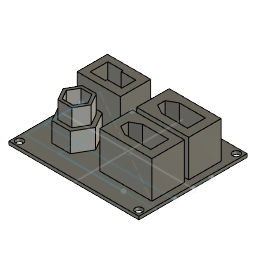
Direct source connector mount (Autodesk Fusion 360 design; units mm, degrees)
Autodesk Fusion 360 part; units mm, degrees
sketch "Sketch1" plane through (0, 0, 0) normal (0, 0, 1) x (1, 0, 0)
  line L0 (0, 0) -> (60, 0)
  line L1 (60, 0) -> (60, 50)
  line L2 (60, 50) -> (0, 50)
  line L3 (0, 50) -> (0, 0)
  dimension "d1" = 60
  dimension "d2" = 50
  constraint horizontal L0
  constraint vertical L1
  constraint horizontal L2
  constraint vertical L3
  constraint coincident L0.start L3.end
  measures "d1" distance of L0.start L0.end
  measures "d2" distance of L0.start L2.end
extrude "Extrude1" add sketch "Sketch1" along normal blind 1.5
sketch "Sketch2" plane through (0, 0, 0) normal (0, 0, -1) x (1, 0, 0)
  line L0 (0, 0) -> (0, -50)
  line L1 (0, -50) -> (60, -50)
  line L2 (60, -50) -> (60, 0)
  line L3 (60, 0) -> (0, 0)
  line L4 (30, -50) -> (30, 0)
  line L5 (60, -25) -> (0, -25)
  line L6 (60, -8) -> (0, -8)
  line L7 (0, -8) -> (0, -42)
  line L8 (60, -8) -> (0, -42) construction
  point P0 (30, -25)
  dimension "d6" = 34
  constraint midpoint L1 L4.start
  constraint midpoint L3 L4.end
  constraint midpoint L2 L5.start
  constraint midpoint L0 L5.end
  constraint horizontal L6
  constraint perpendicular L6 L7
  constraint coincident L8 P0
  constraint midpoint L4 P0
  measures "d6" distance of L6.end L7.end
sketch "Sketch3" plane through (0, 0, 0) normal (0, 0, -1) x (1, 0, 0)
  line L0 (60, -25) -> (60, -33.5)
  line L1 (0, -33.5) -> (0, -16.5)
  line L2 (0, -16.5) -> (60, -16.5)
  dimension "d7" = 8.5
  dimension "d8" = 17
  constraint vertical L0
  measures "d7" distance of L0.start L0.end
  measures "d8" distance of L0.end L2.end
sketch "Sketch4" plane through (0, 0, 0) normal (0, 0, -1) x (1, 0, 0)
  line L0 (45, -8) -> (15, -8)
  line L1 (15, -8) -> (15, -42)
  constraint perpendicular L0 L1
sketch "Sketch5" plane through (0, 0, 0) normal (0, 0, -1) x (1, 0, 0)
  line L0 (36.9, -29.4) -> (53.1, -29.4)
  line L1 (53.1, -29.4) -> (53.1, -37.6)
  line L2 (53.1, -37.6) -> (36.9, -37.6)
  line L3 (36.9, -37.6) -> (36.9, -29.4)
  line L4 (36.9, -29.4) -> (53.1, -37.6) construction
  line L5 (53.1, -29.4) -> (36.9, -37.6) construction
  line L6 (36.9, -33.5) -> (36.9, -32)
  line L7 (36.9, -33.5) -> (36.9, -31.75)
  line L8 (36.9, -31.75) -> (36.9, -35.25)
  line L9 (53.1, -37.6) -> (41.1, -37.6)
  line L10 (53.1, -29.4) -> (41.1, -29.4)
  line L11 (36.9, -31.75) -> (41.1, -29.4)
  line L12 (36.9, -35.25) -> (41.1, -37.6)
  line L13 (36.9, -12.4) -> (53.1, -12.4)
  line L14 (36.9, -16.5) -> (36.9, -15)
  line L15 (36.9, -18.25) -> (41.1, -20.6)
  line L16 (36.9, -14.75) -> (36.9, -18.25)
  line L17 (36.9, -20.6) -> (36.9, -12.4)
  line L18 (53.1, -12.4) -> (41.1, -12.4)
  line L19 (36.9, -12.4) -> (53.1, -20.6) construction
  line L20 (53.1, -20.6) -> (36.9, -20.6)
  line L21 (53.1, -20.6) -> (41.1, -20.6)
  line L22 (53.1, -12.4) -> (53.1, -20.6)
  line L23 (53.1, -12.4) -> (36.9, -20.6) construction
  line L24 (36.9, -14.75) -> (41.1, -12.4)
  line L25 (36.9, -16.5) -> (36.9, -14.75)
  line L26 (8.125, -29.46) -> (21.875, -29.46)
  line L27 (21.875, -29.46) -> (21.875, -37.54)
  line L28 (21.875, -37.54) -> (8.125, -37.54)
  line L29 (8.125, -37.54) -> (8.125, -29.46)
  line L30 (8.125, -29.46) -> (21.875, -37.54) construction
  line L31 (21.875, -29.46) -> (8.125, -37.54) construction
  line L32 (8.125, -37.54) -> (15.125, -37.54)
  line L33 (15.125, -37.54) -> (15.125, -29.46)
  line L34 (15.125, -29.46) -> (8.125, -29.46)
  line L35 (8.125, -29.46) -> (8.125, -37.54)
  line L36 (21.875, -33.5) -> (15, -33.5)
  line L37 (21.875, -36.7) -> (15, -36.7)
  line L38 (15, -36.7) -> (15, -30.3)
  line L39 (15, -30.3) -> (21.875, -30.3)
  line L40 (21.875, -30.3) -> (21.875, -36.7)
  line L41 (21.875, -36.7) -> (15, -30.3) construction
  line L42 (15, -36.7) -> (21.875, -30.3) construction
  point P0 (45, -33.5)
  point P1 (45, -16.5)
  point P2 (15, -33.5)
  point P3 (18.4375, -33.5)
  dimension "d9" = 16.2
  dimension "d10" = 8.2
  dimension "d11" = 1.75
  dimension "d12" = 3.5
  dimension "d13" = 12
  dimension "d14" = 12
  dimension "d15" = 16.2
  dimension "d16" = 8.2
  dimension "d17" = 1.75
  dimension "d18" = 3.5
  dimension "d19" = 12
  dimension "d20" = 12
  dimension "d21" = 13.75
  dimension "d22" = 8.08
  dimension "d23" = 7
  dimension "d24" = 8.08
  dimension "d25" = 6.875
  dimension "d26" = 6.4
  constraint horizontal L0
  constraint perpendicular L0 L1
  constraint parallel L0 L2
  constraint parallel L1 L3
  constraint coincident L4 P0
  constraint coincident L5 P0
  constraint midpoint L3 L6.start
  constraint coincident L3 L6.end
  constraint coincident L3 L7.end
  constraint parallel L3 L8
  constraint coincident L2 L9.end
  constraint coincident L0 L10.end
  constraint horizontal L13
  constraint perpendicular L13 L22
  constraint parallel L13 L20
  constraint parallel L17 L22
  constraint coincident P1 L19
  constraint coincident P1 L23
  constraint midpoint L14.start L17
  constraint coincident L14.end L17
  constraint coincident L16.start L17
  constraint parallel L16 L17
  constraint coincident L15.end L20
  constraint coincident L18.end L13
  constraint horizontal L26
  constraint perpendicular L26 L27
  constraint parallel L26 L28
  constraint parallel L27 L29
  constraint coincident L30 P2
  constraint coincident L31 P2
  constraint horizontal L32
  constraint vertical L33
  constraint horizontal L34
  constraint vertical L35
  constraint midpoint L27 L36.start
  constraint coincident P2 L36.end
  constraint horizontal L37
  constraint perpendicular L37 L38
  constraint parallel L37 L39
  constraint parallel L38 L40
  constraint coincident L41 P3
  constraint coincident L42 P3
  constraint midpoint L36 P3
  measures "d9" distance of L1.end L2.end
  measures "d10" distance of L0.end L1.end
  measures "d11" distance of L6.start L7.end
  measures "d12" distance of L7.end L8.end
  measures "d13" distance of L1.end L9.end
  measures "d14" distance of L0.end L10.end
  measures "d15" distance of L19.end L17.start
  measures "d16" distance of L19.end L13.end
  measures "d17" distance of L14.start L16.start
  measures "d18" distance of L15.start L16.start
  measures "d19" distance of L19.end L15.end
  measures "d20" distance of L13.end L18.end
  measures "d21" distance of L27.end L28.end
  measures "d22" distance of L26.end L27.end
  measures "d23" distance of L28.end L32.end
  measures "d24" distance of L28.end L26.start
  measures "d25" distance of L38.end L39.end
  measures "d26" distance of L37.end L38.end
sketch "Sketch6" plane through (0, 0, 0) normal (0, 0, -1) x (1, 0, 0)
  circle A0 centre (15, -16.5) radius 5
  line L0 (20, -16.5) -> (17.5, -12.1699)
  line L1 (17.5, -12.1699) -> (12.5, -12.1699)
  line L2 (12.5, -12.1699) -> (10, -16.5)
  line L3 (10, -16.5) -> (12.5, -20.8301)
  line L4 (12.5, -20.8301) -> (17.5, -20.8301)
  line L5 (17.5, -20.8301) -> (20, -16.5)
  point P0 (15, -16.5)
  dimension "d27" = 10
  dimension "d28" = 5
  constraint coincident A0 L4.end
  constraint coincident A0 L0.start
  measures "d27" diameter of A0
  measures "d28" distance of L0.start L4.end
sketch "Sketch7" plane through (0, 0, 1.5) normal (0, 0, 1) x (-1, 0, 0)
  line L0 (0, -50) -> (0, 0)
  line L1 (0, 0) -> (-60, 0)
  line L2 (-60, 0) -> (-60, -50)
  line L3 (-60, -50) -> (0, -50)
  line L4 (-22.5, -38) -> (-7.5, -38)
  line L5 (-7.5, -38) -> (-7.5, -29)
  line L6 (-7.5, -29) -> (-22.5, -29)
  line L7 (-22.5, -29) -> (-22.5, -38)
  line L8 (-22.5, -38) -> (-7.5, -29) construction
  line L9 (-7.5, -38) -> (-22.5, -29) construction
  line L10 (-55, -11) -> (-35, -11)
  line L11 (-35, -11) -> (-35, -22)
  line L12 (-35, -22) -> (-55, -22)
  line L13 (-55, -22) -> (-55, -11)
  line L14 (-55, -28) -> (-35, -28)
  line L15 (-35, -28) -> (-35, -39)
  line L16 (-35, -39) -> (-55, -39)
  line L17 (-55, -39) -> (-55, -28)
  line L18 (-18.2501, -22.1291) -> (-11.7501, -22.1292)
  line L19 (-11.7501, -22.1292) -> (-8.5, -16.5001)
  line L20 (-8.5, -16.5001) -> (-11.7499, -10.8709)
  line L21 (-11.7499, -10.8709) -> (-18.2499, -10.8708)
  line L22 (-18.2499, -10.8708) -> (-21.5, -16.4999)
  line L23 (-21.5, -16.4999) -> (-18.2501, -22.1291)
  point P0 (-15, -33.5)
  point P1 (-15, -16.5)
  dimension "d29" = 6.5
  constraint horizontal L4
  constraint perpendicular L4 L5
  constraint parallel L4 L6
  constraint parallel L5 L7
  constraint coincident L8 P0
  constraint coincident L9 P0
  constraint horizontal L10
  constraint vertical L11
  constraint horizontal L12
  constraint vertical L13
  constraint horizontal L14
  constraint vertical L15
  constraint horizontal L16
  constraint vertical L17
  measures "d29" distance of L18.start P1
extrude "Extrude2" add sketch "Sketch7" along normal blind 17 contours L4 L5 L6 L7 | L10 L11 L12 L13 | L14 L15 L16 L17 | L18 L19 L20 L21 L22 L23
extrude "Extrude3" cut sketch "Sketch5" sketch "Sketch6" against normal blind 234872335 contours L0 L1 L2 L3 L6 L7 L8 L9 L10 L11 L12 | L13 L14 L15 L16 L17 L18 L20 L21 L22 L24 L25 | L26 L28 L29 L32 L33 L34 L35 L37 L38 L39 | L27 L33 L36 L39 L40 | L27 L33 L36 L37 L40 of sketch 2 contours L0 L1 L2 L3 L4 L5
extrude "Extrude4" cut 1 faces at (15.125, 34.5667, 12.3333) along direction (-1, 0, 0) blind 1
sketch "Sketch8" plane through (0, 0, 0) normal (0, 0, -1) x (1, 0, 0)
  line L0 (53.6, -38.1) -> (53.6, -28.9)
  line L1 (53.6, -28.9) -> (41.1, -28.9)
  line L2 (36.9, -31.75) -> (36.4, -31.75)
  line L3 (41.1, -28.9) -> (36.4639, -31.491)
  line L4 (41.1, -28.9) -> (46.411, -28.9) construction
  line L5 (53.6, -38.1) -> (41.1, -38.1)
  line L6 (41.1, -38.1) -> (36.4639, -35.509)
  line L7 (36.4639, -35.509) -> (36.4639, -31.491)
  line L8 (36.4639, -18.509) -> (36.4639, -14.491)
  line L9 (41.1, -11.9) -> (46.411, -11.9) construction
  line L10 (53.6, -21.1) -> (53.6, -11.9)
  line L11 (53.6, -21.1) -> (41.1, -21.1)
  line L12 (53.6, -11.9) -> (41.1, -11.9)
  line L13 (41.1, -11.9) -> (36.4639, -14.491)
  line L14 (36.9, -14.75) -> (36.4, -14.75)
  line L15 (41.1, -21.1) -> (36.4639, -18.509)
  line L16 (23, -39) -> (7, -39)
  line L17 (7, -39) -> (7, -28)
  line L18 (7, -28) -> (23, -28)
  line L19 (23, -28) -> (23, -39)
  circle A0 centre (15, -16.5) radius 6
  dimension "d36" = 9.2
  dimension "d37" = 0.5
  dimension "d38" = 150.8
  dimension "d39" = 5.311
  dimension "d40" = 150.8
  dimension "d41" = 9.2
  dimension "d42" = 0.5
  dimension "d43" = 150.8
  dimension "d44" = 5.311
  dimension "d45" = 150.8
  dimension "d46" = 12
  constraint perpendicular L0 L1
  constraint perpendicular L0 L2
  constraint horizontal L4
  constraint perpendicular L0 L5
  constraint perpendicular L2 L7
  constraint perpendicular L10 L12
  constraint perpendicular L10 L14
  constraint horizontal L9
  constraint perpendicular L10 L11
  constraint perpendicular L8 L14
  constraint horizontal L16
  constraint vertical L17
  constraint horizontal L18
  constraint vertical L19
  measures "d36" distance of L0.start L0.end
  measures "d37" distance of L2.start L2.end
  measures "d38" angle of L3 L4
  measures "d39" distance of L1.end L3.end
  measures "d40" angle of L5 L6
  measures "d41" distance of L10.start L10.end
  measures "d42" distance of L14.start L14.end
  measures "d43" angle of L9 L13
  measures "d44" distance of L8.end L9.start
  measures "d45" angle of L11 L15
  measures "d46" diameter of A0
sketch "Sketch9" plane through (0, 0, 0) normal (0, 0, -1) x (1, 0, 0)
  line L0 (57.5, -2.5) -> (2.5, -2.5)
  line L1 (2.5, -2.5) -> (2.5, -47.5)
  line L2 (2.5, -47.5) -> (57.5, -47.5)
  line L3 (57.5, -47.5) -> (57.5, -2.5)
  line L4 (57.5, -2.5) -> (2.5, -47.5) construction
  line L5 (2.5, -2.5) -> (57.5, -47.5) construction
  circle A0 centre (57.5, -47.5) radius 1.7
  circle A1 centre (2.5, -47.5) radius 1.7
  circle A2 centre (57.5, -2.5) radius 1.7
  circle A3 centre (2.5, -2.5) radius 1.7
  point P0 (30, -25)
  dimension "d47" = 55
  dimension "d48" = 45
  dimension "d49" = 3.4
  dimension "d50" = 3.4
  dimension "d51" = 3.4
  dimension "d52" = 3.4
  constraint horizontal L0
  constraint perpendicular L0 L1
  constraint parallel L0 L2
  constraint parallel L1 L3
  constraint coincident L4 P0
  constraint coincident L5 P0
  constraint coincident L2.end L3.start
  constraint coincident L1.end L2.start
  constraint coincident L0.start L3.end
  constraint coincident L0.end L1.start
  measures "d47" distance of L1.end L2.end
  measures "d48" distance of L0.end L1.end
  measures "d49" diameter of A0
  measures "d50" diameter of A1
  measures "d51" diameter of A2
  measures "d52" diameter of A3
extrude "Extrude5" cut sketch "Sketch9" against normal blind 6767 contours L0 L1 A3 | L0 L1 A3 | L0 L3 A2 | L0 L3 A2 | L1 L2 A1 | L1 L2 A1 | L2 L3 A0 | L2 L3 A0
sketch "Sketch10" plane through (0, 0, 1.5) normal (0, 0, 1) x (-1, 0, 0)
  line L0 (0, -50) -> (0, 0)
  line L1 (0, 0) -> (-60, 0)
  line L2 (-60, 0) -> (-60, -50)
  line L3 (-60, -50) -> (0, -50)
  line L4 (-21.5, -16.4999) -> (-18.2499, -10.8708)
  line L5 (-18.2499, -10.8708) -> (-11.7499, -10.8709)
  line L6 (-11.7499, -10.8709) -> (-8.5, -16.5001)
  line L7 (-8.5, -16.5001) -> (-11.7501, -22.1292)
  line L8 (-11.7501, -22.1292) -> (-18.2501, -22.1291)
  line L9 (-18.2501, -22.1291) -> (-21.5, -16.4999)
  line L10 (-55, -39) -> (-55, -28)
  line L11 (-55, -28) -> (-35, -28)
  line L12 (-35, -28) -> (-35, -39)
  line L13 (-35, -39) -> (-55, -39)
  line L14 (-22.5, -29) -> (-7.5, -29)
  line L15 (-7.5, -29) -> (-7.5, -38)
  line L16 (-7.5, -38) -> (-22.5, -38)
  line L17 (-22.5, -38) -> (-22.5, -29)
  line L18 (-55, -22) -> (-55, -11)
  line L19 (-55, -11) -> (-35, -11)
  line L20 (-35, -11) -> (-35, -22)
  line L21 (-35, -22) -> (-55, -22)
  circle A0 centre (-57.5, -2.5) radius 1.7
  circle A1 centre (-57.5, -47.5) radius 1.7
  circle A2 centre (-2.5, -2.5) radius 1.7
  circle A3 centre (-2.5, -47.5) radius 1.7
  line L22 (-23.5, -16.4999) -> (-19.2501, -23.8612)
  line L23 (-19.2501, -23.8612) -> (-10.7501, -23.8613)
  line L24 (-10.7501, -23.8613) -> (-6.5, -16.5001)
  line L25 (-6.5, -16.5001) -> (-10.7499, -9.1388)
  line L26 (-10.7499, -9.1388) -> (-19.2499, -9.1387)
  line L27 (-19.2499, -9.1387) -> (-23.5, -16.4999)
  point P0 (-15, -16.5)
  dimension "d55" = 8.5
  measures "d55" distance of L22.start P0
extrude "Extrude6" add sketch "Sketch10" along normal blind 9 contours L22 L23 L24 L25 L26 L27
extrude "Extrude7" cut sketch "Sketch8" against normal blind 8 contours A0
extrude "Extrude8" add 1 faces at (41.6667, 22, 7.1667) along direction (0, 1, 0) blind 2
extrude "Extrude9" add 1 faces at (48.3333, 11, 7.1667) along direction (0, -1, 0) blind 2
extrude "Extrude10" add 1 faces at (55, 14, 7.1667) along direction (1, 0, 0) blind 2
extrude "Extrude11" add 1 faces at (35, 19, 7.1667) along direction (-1, 0, 0) blind 2
extrude "Extrude12" add 1 faces at (48.3333, 28, 7.1667) along direction (0, -1, 0) blind 2
extrude "Extrude13" add 1 faces at (55, 34.6667, 7.1667) along direction (1, 0, 0) blind 2
extrude "Extrude14" add 1 faces at (49.6667, 39, 12.8333) along direction (0, 1, 0) blind 2
extrude "Extrude15" add 1 faces at (35, 36, 7.1667) along direction (-1, 0, 0) blind 2
sketch "Sketch11" plane through (0, 0, 0) normal (0, 0, -1) x (1, 0, 0)
  line L0 (53.1, -12.4) -> (54.1, -12.4)
  line L1 (53.1, -12.4) -> (53.1, -11.4)
  line L2 (53.1, -20.6) -> (54.1, -20.6)
  line L3 (53.1, -20.6) -> (53.1, -21.6)
  line L4 (41.1, -20.6) -> (41.1, -21.6)
  line L5 (41.1, -12.4) -> (41.1, -11.4)
  line L6 (36.9, -14.75) -> (35.9, -14.75)
  line L7 (36.9, -18.25) -> (35.9, -18.25)
  line L8 (35.9, -18.25) -> (41.1, -21.6)
  line L9 (41.1, -21.6) -> (53.1, -21.6)
  line L10 (53.1, -21.6) -> (54.1, -21.6)
  line L11 (54.1, -21.6) -> (54.1, -20.6)
  line L12 (54.1, -20.6) -> (54.1, -12.4)
  line L13 (54.1, -12.4) -> (54.1, -11.4)
  line L14 (54.1, -11.4) -> (41.1, -11.4)
  line L15 (41.1, -11.4) -> (35.9, -14.75)
  line L16 (35.9, -14.75) -> (35.9, -18.25)
  line L17 (54.1, -37.6) -> (54.1, -29.4)
  line L18 (54.1, -28.4) -> (41.1, -28.4)
  line L19 (41.1, -28.4) -> (35.9, -31.75)
  line L20 (35.9, -31.75) -> (35.9, -35.25)
  line L21 (35.9, -35.25) -> (41.1, -38.6)
  line L22 (41.1, -38.6) -> (53.1, -38.6)
  line L23 (54.1, -29.4) -> (54.1, -28.4)
  line L24 (53.1, -38.6) -> (54.1, -38.6)
  line L25 (54.1, -38.6) -> (54.1, -37.6)
  dimension "d76" = 1
  dimension "d77" = 1
  dimension "d78" = 1
  dimension "d79" = 1
  dimension "d80" = 1
  dimension "d81" = 1
  dimension "d82" = 1
  dimension "d83" = 1
  constraint horizontal L0
  constraint perpendicular L0 L1
  constraint horizontal L2
  constraint perpendicular L2 L3
  constraint vertical L4
  constraint vertical L5
  constraint horizontal L6
  constraint horizontal L7
  constraint perpendicular L3 L10
  constraint perpendicular L2 L11
  constraint perpendicular L0 L13
  constraint perpendicular L5 L14
  constraint perpendicular L7 L16
  measures "d76" distance of L0.start L0.end
  measures "d77" distance of L0.start L1.end
  measures "d78" distance of L2.start L2.end
  measures "d79" distance of L2.start L3.end
  measures "d80" distance of L4.start L4.end
  measures "d81" distance of L5.start L5.end
  measures "d82" distance of L6.start L6.end
  measures "d83" distance of L7.start L7.end
extrude "Extrude16" cut sketch "Sketch11" against normal blind 9
sketch "Sketch12" plane through (0, 0, 0) normal (0, 0, -1) x (1, 0, 0)
extrude "Extrude17" add 1 faces at (12.5, 29, 7.1667) along direction (0, -1, 0) blind 2.5
extrude "Extrude18" add 1 faces at (7.5, 30.3333, 12.8333) along direction (-1, 0, 0) blind 2.5
extrude "Extrude19" add 1 faces at (16.6667, 38, 7.1667) along direction (0, 1, 0) blind 2.5
extrude "Extrude20" add 1 faces at (22.5, 35.8333, 12.8333) along direction (1, 0, 0) blind 2.5
sketch "Sketch13" plane through (0, 0, 0) normal (0, 0, -1) x (1, 0, 0)
equation "d6 = 50 mm - 16 mm"
equation "d7 = ( 17 / 2 ) * 1 mm"
equation "d11 = ( 3.5 / 2 ) * 1 mm"
equation "d17 = ( 3.5 / 2 ) * 1 mm"
equation "d36 = 8.7 mm + 0.5 mm"
equation "d39 = 4.811 mm + 0.5 mm"
equation "d41 = 8.7 mm + 0.5 mm"
equation "d44 = 4.811 mm + 0.5 mm"
